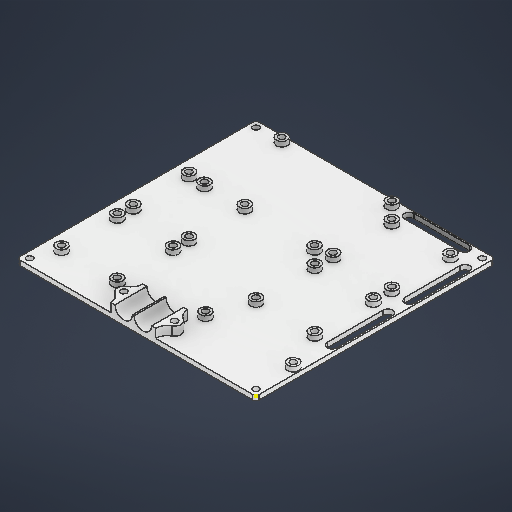
# Autodesk Inventor part: Power board
Saved by Autodesk Inventor 2026.2 (Build 302298010, 298A)
## iProperties
Created: 2026-04-28
Part Number: Power board
Material: ABS 플라스틱
Document SubType Name: Modeling
Designer: work
Density: 1.06 g/cm^3
Appearance: 매끄러움 - 흰색
Author: work
Autodesk Inventor part; units mm, degrees
ref_plane "YZ Plane" through (0, 0, 0) normal (1, 0, 0) x (0, 1, 0)
ref_plane "XZ Plane" through (0, 0, 0) normal (0, 1, 0) x (-1, 0, 0)
ref_plane "XY Plane" through (0, 0, 0) normal (0, 0, 1) x (1, 0, 0)
sketch "스케치1" plane through (0, 0, 0) normal (0, 1, 0) x (-1, 0, 0)
  line L0 (0, -150) -> (150, -150)
  line L1 (150, -150) -> (150, 0)
  line L2 (150, 0) -> (0, 0)
  line L3 (0, 0) -> (0, -150)
  line L4 (0, -150) -> (150, 0) construction
  line L5 (150, -150) -> (0, 0) construction
  line L6 (4, -4) -> (146, -4) construction
  line L7 (146, -4) -> (146, -146) construction
  line L8 (146, -146) -> (4, -146) construction
  line L9 (4, -146) -> (4, -4) construction
  line L10 (4, -4) -> (146, -146) construction
  line L11 (146, -4) -> (4, -146) construction
  line L12 (14, -99.2) -> (50.8, -99.2) construction
  line L13 (50.8, -99.2) -> (50.8, -136) construction
  line L14 (50.8, -136) -> (14, -136) construction
  line L15 (14, -136) -> (14, -99.2) construction
  line L16 (14, -99.2) -> (50.8, -136) construction
  line L17 (50.8, -99.2) -> (14, -136) construction
  circle A0 centre (14, -99.2) radius 2
  circle A1 centre (14, -136) radius 2
  circle A2 centre (50.8, -136) radius 2
  circle A3 centre (50.8, -99.2) radius 2
  line L18 (14.9, -146) -> (49.9, -146) construction
  line L19 (14.9, -149) -> (49.9, -149)
  line L20 (49.9, -143) -> (14.9, -143)
  arc A4 (14.9, -143) -> (14.9, -149) centre (14.9, -146) ccw
  arc A5 (49.9, -149) -> (49.9, -143) centre (49.9, -146) ccw
  line L21 (32.4, -117.6) -> (32.4, -146) construction
  line L22 (50.8, -50.8321) -> (50.8, -87.6321) construction
  line L23 (14, -50.8321) -> (50.8, -50.8321) construction
  line L24 (50.8, -50.8321) -> (14, -87.6321) construction
  line L25 (50.8, -87.6321) -> (14, -50.8321) construction
  line L26 (14, -87.6321) -> (14, -50.8321) construction
  line L27 (50.8, -87.6321) -> (14, -87.6321) construction
  circle A6 centre (50.8, -50.8321) radius 2
  circle A7 centre (14, -50.8321) radius 2
  circle A8 centre (14, -87.6321) radius 2
  circle A9 centre (50.8, -87.6321) radius 2
  arc A10 (7, -51.7321) -> (1, -51.7321) centre (4, -51.7321) ccw
  line L28 (32.4, -69.2321) -> (4, -69.2321) construction
  line L29 (4, -86.7321) -> (4, -51.7321) construction
  line L30 (7, -86.7321) -> (7, -51.7321)
  arc A11 (1, -86.7321) -> (7, -86.7321) centre (4, -86.7321) ccw
  line L31 (1, -51.7321) -> (1, -86.7321)
  line L32 (60.8, -97.5) -> (129.8, -97.5) construction
  line L33 (129.8, -97.5) -> (129.8, -146) construction
  line L34 (129.8, -146) -> (60.8, -146) construction
  line L35 (60.8, -146) -> (60.8, -97.5) construction
  line L36 (60.8, -97.5) -> (129.8, -146) construction
  line L37 (129.8, -97.5) -> (60.8, -146) construction
  circle A12 centre (60.8, -97.5) radius 2
  circle A13 centre (60.8, -146) radius 2
  circle A14 centre (129.8, -146) radius 2
  circle A15 centre (129.8, -97.5) radius 2
  line L38 (59, -27.3321) -> (4, -27.3321) construction
  line L39 (8.5, -13.8321) -> (54.5, -13.8321) construction
  line L40 (54.5, -13.8321) -> (54.5, -40.8321) construction
  line L41 (54.5, -40.8321) -> (8.5, -40.8321) construction
  line L42 (8.5, -40.8321) -> (8.5, -13.8321) construction
  line L43 (8.5, -13.8321) -> (54.5, -40.8321) construction
  line L44 (54.5, -13.8321) -> (8.5, -40.8321) construction
  circle A16 centre (59, -27.3321) radius 2
  circle A17 centre (4, -27.3321) radius 2
  circle A18 centre (4, -4) radius 2
  circle A19 centre (4, -146) radius 2
  circle A20 centre (146, -146) radius 2
  circle A21 centre (146, -4) radius 2
  line L45 (4, -135.1) -> (4, -100.1) construction
  line L46 (7, -135.1) -> (7, -100.1)
  line L47 (1, -100.1) -> (1, -135.1)
  arc A22 (1, -135.1) -> (7, -135.1) centre (4, -135.1) ccw
  arc A23 (7, -100.1) -> (1, -100.1) centre (4, -100.1) ccw
  line L48 (105, -18) -> (140, -18) construction
  line L49 (140, -18) -> (140, -53) construction
  line L50 (140, -53) -> (105, -53) construction
  line L51 (105, -53) -> (105, -18) construction
  line L52 (105, -18) -> (140, -53) construction
  line L53 (140, -18) -> (105, -53) construction
  line L54 (105, -35.5) -> (140, -35.5) construction
  line L55 (122.5, -53) -> (122.5, -18) construction
  circle A24 centre (140, -18) radius 2
  circle A25 centre (140, -53) radius 2
  circle A26 centre (105, -53) radius 2
  circle A27 centre (105, -18) radius 2
  line L56 (105, -63) -> (140, -63) construction
  line L57 (140, -63) -> (140, -98) construction
  line L58 (140, -98) -> (105, -98) construction
  line L59 (105, -98) -> (105, -63) construction
  line L60 (105, -63) -> (140, -98) construction
  line L61 (140, -63) -> (105, -98) construction
  line L62 (105, -80.5) -> (140, -80.5) construction
  line L63 (122.5, -98) -> (122.5, -63) construction
  circle A28 centre (140, -63) radius 2
  circle A29 centre (140, -98) radius 2
  circle A30 centre (105, -98) radius 2
  circle A31 centre (105, -63) radius 2
  point P0 (75, -75)
  point P1 (32.4, -87.6321)
  point P2 (95.3, -121.75)
  point P3 (31.5, -27.3321)
  point P4 (4, -117.6)
  point P5 (122.5, -35.5)
  point P6 (122.5, -80.5)
  dimension "d0" = 150
  dimension "d1" = 150
  dimension "d2" = 4
  dimension "d3" = 36.8
  dimension "d4" = 36.8
  dimension "d5" = 4
  dimension "d6" = 4
  dimension "d7" = 4
  dimension "d8" = 4
  dimension "d9" = 6
  dimension "d10" = 35
  dimension "d11" = 10
  dimension "d12" = 10
  dimension "d13" = 36.8
  dimension "d14" = 36.8
  dimension "d15" = 4
  dimension "d16" = 4
  dimension "d17" = 4
  dimension "d18" = 4
  dimension "d19" = 6
  dimension "d20" = 35
  dimension "d21" = 28.4
  dimension "d22" = 69
  dimension "d23" = 48.5
  dimension "d24" = 4
  dimension "d25" = 4
  dimension "d26" = 4
  dimension "d27" = 4
  dimension "d28" = 10
  dimension "d29" = 11.5679
  dimension "d30" = 55
  dimension "d31" = 46
  dimension "d32" = 27
  dimension "d33" = 4
  dimension "d34" = 4
  dimension "d35" = 10
  dimension "d36" = 4
  dimension "d37" = 4
  dimension "d38" = 4
  dimension "d39" = 4
  dimension "d40" = 17.5
  dimension "d41" = 6
  dimension "d48" = 35
  dimension "d49" = 35
  dimension "d50" = 14
  dimension "d51" = 6
  dimension "d52" = 4
  dimension "d53" = 4
  dimension "d54" = 4
  dimension "d55" = 4
  dimension "d56" = 35
  dimension "d57" = 35
  dimension "d58" = 4
  dimension "d59" = 4
  dimension "d60" = 4
  dimension "d61" = 4
  dimension "d62" = 10
  constraints: 134 end point, 32 centre point, 29 midpoint, 27 coincident, 19 parallel, 12 point on circle, 12 tangent, 10 horizontal, 8 perpendicular, 7 point on line, 2 vertical, 1 collinear
  measures "d0" distance of L2.end L1.end
  measures "d1" distance of L1.end L0.end
  measures "d2" distance between parallel lines of L1 L7
  measures "d3" distance of L13.end L14.end
  measures "d4" distance of L13.start L13.end
  measures "d5" diameter of A0
  measures "d6" diameter of A1
  measures "d7" diameter of A2
  measures "d8" diameter of A3
  measures "d9" diameter of A5
  measures "d10" distance of L18.start L18.end
  measures "d11" horizontal distance of L8.end A1.centre
  measures "d12" horizontal distance of L8.end L14.end
  measures "d13" distance of L26.start L26.end
  measures "d14" distance of L27.start L26.start
  measures "d15" diameter of A6
  measures "d16" diameter of A7
  measures "d17" diameter of A8
  measures "d18" diameter of A9
  measures "d19" diameter of A10
  measures "d20" distance of L29.start L29.end
  measures "d21" distance of L28.start L28.end
  measures "d22" distance of L34.start L35.start
  measures "d23" distance of L32.end L34.start
  measures "d24" diameter of A12
  measures "d25" diameter of A13
  measures "d26" diameter of A14
  measures "d27" diameter of A15
  measures "d28" distance between parallel lines of L13 L35
  measures "d29" distance between parallel lines of L12 L27
  measures "d30" distance of L38.start L38.end
  measures "d31" distance of L40.end L44.end
  measures "d32" distance of L39.end L40.end
  measures "d33" diameter of A16
  measures "d34" diameter of A17
  measures "d35" distance between parallel lines of L23 L41
  measures "d36" diameter of A18
  measures "d37" diameter of A19
  measures "d38" diameter of A20
  measures "d39" diameter of A21
  measures "d40" distance of point (4, -117.6) L45.end
  measures "d41" diameter of A23
  measures "d48" distance of L49.end L50.end
  measures "d49" distance of L48.end L49.end
  measures "d50" distance between parallel lines of L6 L48
  measures "d51" distance between parallel lines of L7 L49
  measures "d52" diameter of A24
  measures "d53" diameter of A25
  measures "d54" diameter of A26
  measures "d55" diameter of A27
  measures "d56" distance of L58.start L58.end
  measures "d57" distance of L57.start L58.start
  measures "d58" diameter of A28
  measures "d59" diameter of A29
  measures "d60" diameter of A30
  measures "d61" diameter of A31
  measures "d62" distance between parallel lines of L56 L50
extrude "돌출1" add sketch "스케치1" along normal blind 3
sketch "스케치2" plane through (0, 3, 0) normal (0, 1, 0) x (1, 0, 0)
  line L0 (-7, 100.1) -> (-7, 135.1) projected
  line L1 (-150, 150) -> (-150, 0) projected
  line L2 (-150, 0) -> (0, 0) projected
  line L3 (0, 0) -> (0, 150) projected
  line L4 (0, 150) -> (-150, 150) projected
  circle A0 centre (-146, 4) radius 2 projected
  circle A1 centre (-4, 146) radius 2 projected
  circle A2 centre (-4, 27.3321) radius 2 projected
  circle A3 centre (-129.8, 146) radius 2 projected
  circle A4 centre (-129.8, 97.5) radius 2 projected
  circle A5 centre (-50.8, 87.6321) radius 2 projected
  circle A6 centre (-50.8, 50.8321) radius 2 projected
  circle A7 centre (-14, 87.6321) radius 2 projected
  circle A8 centre (-14, 50.8321) radius 2 projected
  circle A9 centre (-50.8, 136) radius 2 projected
  circle A10 centre (-14, 136) radius 2 projected
  circle A11 centre (-14, 99.2) radius 2 projected
  circle A12 centre (-50.8, 99.2) radius 2 projected
  circle A13 centre (-60.8, 97.5) radius 2 projected
  circle A14 centre (-60.8, 146) radius 2 projected
  circle A15 centre (-59, 27.3321) radius 2 projected
  circle A16 centre (-4, 4) radius 2 projected
  circle A17 centre (-146, 146) radius 2 projected
  arc A18 (-1, 135.1) -> (-7, 135.1) centre (-4, 135.1) ccw projected
  line L5 (-1, 135.1) -> (-1, 100.1) projected
  arc A19 (-7, 100.1) -> (-1, 100.1) centre (-4, 100.1) ccw projected
  line L6 (-7, 100.1) -> (-7, 135.1) projected
  line L7 (-7, 51.7321) -> (-7, 86.7321) projected
  arc A20 (-1, 86.7321) -> (-7, 86.7321) centre (-4, 86.7321) ccw projected
  line L8 (-1, 86.7321) -> (-1, 51.7321) projected
  arc A21 (-7, 51.7321) -> (-1, 51.7321) centre (-4, 51.7321) ccw projected
  line L9 (-49.9, 149) -> (-14.9, 149) projected
  arc A22 (-14.9, 143) -> (-14.9, 149) centre (-14.9, 146) ccw projected
  line L10 (-14.9, 143) -> (-49.9, 143) projected
  arc A23 (-49.9, 149) -> (-49.9, 143) centre (-49.9, 146) ccw projected
  circle A24 centre (-14, 87.6321) radius 2 projected
  circle A25 centre (-14, 50.8321) radius 2 projected
  circle A26 centre (-129.8, 146) radius 2 projected
  circle A27 centre (-4, 27.3321) radius 3.5
  circle A28 centre (-105, 18) radius 2 projected
  circle A29 centre (-140, 18) radius 2 projected
  circle A30 centre (-140, 53) radius 2 projected
  circle A31 centre (-105, 53) radius 2 projected
  circle A32 centre (-105, 63) radius 2 projected
  circle A33 centre (-140, 63) radius 2 projected
  circle A34 centre (-140, 98) radius 2 projected
  circle A35 centre (-105, 98) radius 2 projected
  dimension "d44" = 7
  constraints: 23 coincident, 1 centre point
  measures "d44" diameter of A27
extrude "돌출2" add sketch "스케치2" along normal blind 3 contours A27
pattern_sketch "스케치 연계 패턴1" of "돌출2" from (-4, 3, -27.3321) copies at (-14, 3, -136) at (-50.8, 3, -136) at (-60.8, 3, -146) at (-60.8, 3, -97.5) at (-50.8, 3, -99.2) at (-50.8, 3, -87.6321) at (-14, 3, -99.2) at (-14, 3, -87.6321) at (-14, 3, -50.8321) at (-59, 3, -27.3321) at (-50.8, 3, -50.8321) at (-129.8, 3, -97.5) at (-129.8, 3, -146) at (-105, 3, -18) at (-140, 3, -18) at (-140, 3, -53) at (-105, 3, -53) at (-105, 3, -63) at (-105, 3, -98) at (-140, 3, -63) at (-140, 3, -98)
fillet "모깎기1" radius 2 4 edges at (-150, 1.5, 0) (0, 1.5, 0) (0, 1.5, -150) (-150, 1.5, -150)
sketch "스케치3" plane through (0, 3, 0) normal (0, 1, 0) x (1, 0, 0)
  point P0 (0, 0)
sketch "스케치4" plane through (-148, 0, 0) normal (0, 0, 1) x (1, 0, 0)
  line L0 (146, 3) -> (146, 0) projected
  line L1 (0, 3) -> (146, 3) projected
  line L2 (0, 0) -> (0, 3) projected
  line L3 (0, 0) -> (146, 0) projected
  circle A0 centre (65, 8.5) radius 5.5
  circle A1 centre (77, 8.5) radius 5.5
  line L4 (0, 3) -> (146, 3) projected
  line L5 (146, 3) -> (0, 3) projected
  line L6 (57, 3) -> (57, 8.5)
  line L7 (57, 8.5) -> (85, 8.5)
  line L8 (85, 8.5) -> (85, 3)
  line L9 (41, 6) -> (45, 6) projected
  line L10 (41, 0) -> (45, 0) projected
  point P0 (148, 0)
  point P1 (43, 6)
  point P2 (82.5, 8.5)
  point P3 (77, 3)
  point P4 (71.5, 8.5)
  point P5 (70.5, 8.5)
  point P6 (65, 3)
  point P7 (59.5, 8.5)
  dimension "d63" = 11
  dimension "d64" = 11
  dimension "d65" = 12
  dimension "d66" = 8
  dimension "d67" = 8
  dimension "d68" = 28
  dimension "d69" = 14
  constraints: 6 end point, 3 perpendicular, 2 centre point, 2 point on line, 2 tangent, 1 midpoint
  measures "d63" diameter of A0
  measures "d64" diameter of A1
  measures "d65" distance of A1.centre A0.centre
  measures "d66" distance from line of L8 A1.centre
  measures "d67" distance of L6.end A0.centre
  measures "d68" distance of L6.end L7.end
  measures "d69" distance from line of point (43, 6) L6
extrude "돌출3" add sketch "스케치4" against normal blind 20 contours L1 A1 L7 L8 | L1 A0 L7 A1 | L1 L6 L7 A0
sketch "스케치5" plane through (-91, 8.5, 0) normal (0, 1, 0) x (1, 0, 0)
  line L0 (0, 0) -> (0, 20) projected
  line L1 (0, 10) -> (28, 10) construction
  line L2 (28, 20) -> (28, 0) projected
  circle A0 centre (-2, 10) radius 2
  circle A1 centre (30, 10) radius 2
  line L3 (-2, 10) -> (30, 10) construction
  circle A2 centre (-2, 10) radius 4
  circle A3 centre (30, 10) radius 4
  line L4 (25.5, 20) -> (28, 20) projected
  arc A4 (28, 20) -> (31.8824, 13.5294) centre (35.3333, 20) ccw
  line L5 (28, 0) -> (28, 20) projected
  line L6 (-57, 0) -> (89, 0) projected
  line L7 (14, 0) -> (14, 20) construction
  line L8 (14.5, 0) -> (14.5, 20) construction
  line L9 (13.5, 20) -> (14.5, 20) projected
  arc A5 (31.8824, 6.4706) -> (28, 0) centre (35.3333, 0) ccw
  arc A6 (-3.8824, 13.5294) -> (0, 20) centre (-7.3333, 20) ccw
  arc A7 (0, 0) -> (-3.8824, 6.4706) centre (-7.3333, 0) ccw
  point P0 (91, 0)
  point P1 (14, 10)
  point P2 (-3.8824, 13.5294)
  point P3 (-3.8824, 6.4706)
  point P4 (0, 10)
  point P5 (31.8824, 6.4706)
  point P6 (28, 10)
  dimension "d76" = 8
  dimension "d72" = 4
  dimension "d73" = 4
  dimension "d74" = 32
  dimension "d75" = 8
  constraints: 8 point on circle, 7 centre point, 6 end point, 6 symmetric about line, 5 midpoint, 2 coincident, 1 collinear, 1 parallel, 1 point on line, 1 tangent, 7 other
  measures "d72" diameter of A0
  measures "d73" diameter of A1
  measures "d74" distance of L3.end L3.start
  measures "d75" diameter of A2
extrude "돌출4" add sketch "스케치5" against normal up to surface (5.5 mm away) contours A7 A2 L0 | A2 L0 | A6 L0 A2 | A4 A3 L2 | A3 L2 | A3 A5 L2 picked at (-3.8955, 7.2815) picked at (33.3023, 10.286)
